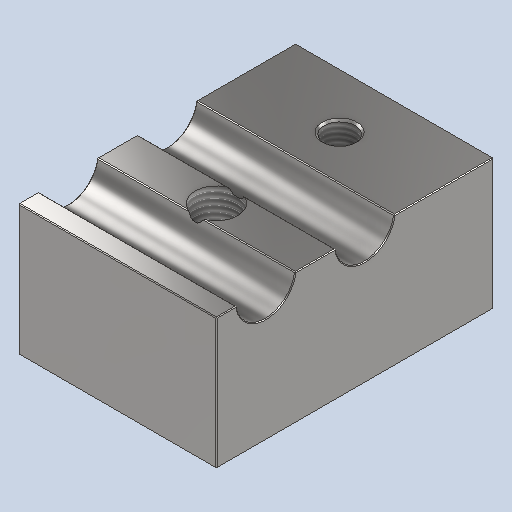
# Autodesk Inventor part: Einspannvorrichtung Hauptbacke
Saved by Autodesk Inventor 2026.2 (Build 302298010, 298A)
## iProperties
Created: 2026-07-28
Part Number: Einspannvorrichtung Hauptbacke
Material: Stahl, Legierung
Document SubType Name: Modeling
Designer: moest
Density: 7.73 g/cm^3
Appearance: Halbpoliert
Author: moest
Autodesk Inventor part; units mm, degrees
ref_plane "YZ Plane" through (0, 0, 0) normal (1, 0, 0) x (0, 1, 0)
ref_plane "XZ Plane" through (0, 0, 0) normal (0, 1, 0) x (-1, 0, 0)
ref_plane "XY Plane" through (0, 0, 0) normal (0, 0, 1) x (1, 0, 0)
sketch "Skizze1" plane through (0, 0, 0) normal (0, 1, 0) x (-1, 0, 0)
  line L0 (0, 0) -> (50, 0)
  line L1 (50, 0) -> (50, -34)
  line L2 (50, -34) -> (0, -34)
  line L3 (0, -34) -> (0, 0)
  dimension "d0" = 50
  dimension "d1" = 34
  constraints: 8 end point, 2 parallel, 1 horizontal, 1 perpendicular
  measures "d0" distance of L1.end L2.end
  measures "d1" distance of L0.end L1.end
extrude "Extrusion1" add sketch "Skizze1" along normal blind 70
sketch "Skizze2" plane through (0, 0, -34) normal (0, 0, -1) x (-1, 0, 0)
  circle A0 centre (25, 56.1) radius 3.9
  line L0 (0, 0) -> (0, 70) projected
  line L1 (0, 70) -> (50, 70) projected
  dimension "d4" = 7.8
  dimension "d5" = 25
  dimension "d6" = 13.9
  constraints: 1 centre point
  measures "d4" diameter of A0
  measures "d5" distance from line of L0 A0.centre
  measures "d6" distance from line of L1 A0.centre
extrude "Extrusion2" cut sketch "Skizze2" against normal blind 70
thread "Gewinde1" size "M8x1.25" class "6H" standard "ANSI Metric M Profile" full length
chamfer "Fasen1" distance 0.5 angle 45 1 edges at (-21.1, 56.1, -34)
chamfer "Fasen2" distance 0.2 angle 45 12 edges at (0, 70, -17) (0, 35, 0) (-25, 70, 0) (-25, 70, -34) (-50, 70, -17) (-50, 35, 0) (-50, 35, -34) (-50, 0, -17) (-25, 0, 0) (0, 35, -34) (0, 0, -17) (-25, 0, -34)
chamfer "Fasen3" distance 0.5 angle 45 1 edges at (-21.1, 56.1, 0)
sketch "Skizze3" plane through (-50, 0.2, -0.2) normal (-1, 0, 0) x (0, 0, 1)
  line L0 (0.2, 69.6) -> (0.2, 0) projected
  circle A0 centre (0.2, 37.3) radius 7.5
  circle A1 centre (0.2, 12.3) radius 7.5
  line L1 (-33.6, -0.2) -> (0, -0.2) projected
  point P0 (0.2, -0.2)
  dimension "d20" = 15
  dimension "d21" = 15
  dimension "d22" = 12.5
  dimension "d23" = 37.5
  constraints: 2 centre point, 1 point on line
  measures "d20" diameter of A0
  measures "d21" diameter of A1
  measures "d22" distance from line of L1 A1.centre
  measures "d23" distance from line of L1 A0.centre
extrude "Extrusion3" cut sketch "Skizze3" against normal blind 70
chamfer "Fasen4" distance 0.2 angle 45 8 edges at (-25, 45, 0) (-25, 30, 0) (-50, 37.5, -7.5) (0, 37.5, -7.5) (-25, 20, 0) (-25, 5, 0) (-50, 12.5, -7.5) (0, 12.5, -7.5)
sketch "Skizze4" plane through (-0.2, 0.2, -34) normal (0, 0, -1) x (-1, 0, 0)
  circle A0 centre (24.8, 24.8) radius 5.4
  line L0 (-0.2, 69.6) -> (-0.2, 0) projected
  line L1 (0, -0.2) -> (49.6, -0.2) projected
  point P0 (-0.2, -0.2)
  dimension "d29" = 10.8
  dimension "d30" = 25
  dimension "d31" = 25
  constraints: 1 centre point
  measures "d29" diameter of A0
  measures "d30" distance from line of L0 A0.centre
  measures "d31" distance from line of L1 A0.centre
extrude "Extrusion4" cut sketch "Skizze4" against normal blind 70
sketch "Skizze5" plane through (-49.8, 69.8, 0) normal (0, 0, 1) x (1, 0, 0)
  line L0 (-0.2, 0.2) -> (49.8, 0.2)
  line L1 (49.8, 0.2) -> (49.8, -69.8)
  line L2 (49.8, -69.8) -> (-0.2, -69.8)
  line L3 (-0.2, -69.8) -> (-0.2, 0.2)
  constraints: 8 end point, 2 parallel, 1 horizontal, 1 perpendicular
extrude "Extrusion5" cut sketch "Skizze5" against normal blind 1
chamfer "Fasen5" distance 0.2 angle 45 14 edges at (-38.3335, 30.067, -1) (-50, 25, -1) (-38.3335, 19.933, -1) (0, 25, -1) (-11.6665, 30.067, -1) (-11.6665, 19.933, -1) (-25, 44.933, -1) (-50, 57.4674, -1) (-25, 70, -1) (0, 57.4674, -1) (-50, 2.5326, -1) (-25, 0, -1) (0, 2.5326, -1) (-25, 5.067, -1)
chamfer "Fasen6" distance 0.5 angle 45 1 edges at (-21.1, 56.1, -1)
thread "Gewinde4" size "M11x1.5" class "6H" standard "ANSI Metric M Profile" full length
